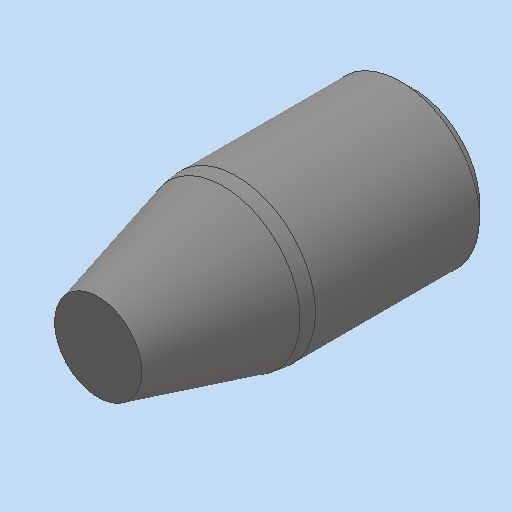
# Autodesk Inventor part: MM0948AN100_G01_125
Saved by Autodesk Inventor 2023.3 (Build 273359000, 359)
## iProperties
Created: 2023-03-23
Part Number: MM0948AN100_G01_125
Material: 1.2379 X155CrVMo12-1
Description: =<RBPARTNOTITLE2>
Document SubType Name: Modeling
Designer: ric7an
Mass: 1.92974 g
Surface Area: 2.93738 cm^2
Volume: 0.245827 cm^3
Density: 7.85 g/cm^3
Appearance: Stahl - rostfrei AnP
AnP_Kategorie: 1
AnP_Material: =<Material>
MaxAbmaße: 6 x 12 x 6 (FM)
AnP_TemplVers: 20200821
RBDOCUMENTTYPE: DRF
RBDOCUMENTVERSION: 00
RBDRAWINGMAINSCALE: 1:1
RBDRAWINGMISSINGSPEC: --
RBDRAWINGVOLUME: --
RBDSV1: 0850
RBGBEDGESIN1: +0,5
RBGBEDGESIN2: +0,2
RBGBEDGESOUT1: -0,3
RBGBEDGESOUT2: -0,1
RBMATERIAL: =<Material>
RBMATMEETS: --
RBMATNO: =<Part Number>
RBPARTMADEOF: Ø6 x 12 (FM)
RBPARTNO: SIEHE MNR
RBPARTNOTITLE1: manufactured part
RBPARTNOTITLE2: Anfertigungsteil
RBPARTSAFETYINDICATOR: --
RBSURFACE: --
RBSURFACE2: --
RBZEDGESNORM: ISO13715:2002-06
RBZGENDIMCLASS: m
RBZGENDIMNORM: ISO 2768-1:1989-11
RBZGENGEOCLASS: H
RBZGENGEONORM: ISO 2768-2:1989-11
RBZSURFACENORM: ISO13D2:2002-02
RBZTOLERANCENORM: ISO 14405-1:2010-12
AnP_Kommentar_aktuell: =<Comments>
AnP_Material_aktuell: =<Material>
Author: FH/Wi
Keywords: =<RBPARTMADEOF>
Comments: =<RBSURFACE2>
Revision Number: 01
Autodesk Inventor part; units mm, degrees
ref_plane "YZ Plane" through (0, 0, 0) normal (1, 0, 0) x (0, 1, 0)
ref_plane "XZ Plane" through (0, 0, 0) normal (0, 1, 0) x (-1, 0, 0)
ref_plane "XY Plane" through (0, 0, 0) normal (0, 0, 1) x (1, 0, 0)
sketch "Skizze1" plane through (0, 0, 0) normal (0, 0, 1) x (1, 0, 0)
  line L0 (0, 14.4) -> (0, -2.4) projected
  line L1 (-3.6, 0) -> (0.6, 0) projected
  line L2 (-1.6603, 0) -> (-3, 5)
  line L3 (-3, 5) -> (-3, 12)
  line L4 (-3, 12) -> (0, 12)
  point P0 (0, 0)
  dimension "d0" = 3
  dimension "d1" = 15
  dimension "d2" = 5
  dimension "d3" = 7
  constraints: 6 end point, 2 point on line, 1 perpendicular, 1 vertical
  measures "d0" distance of L3.end L4.end
  measures "d1" angle of L3 L2
  measures "d2" vertical distance of L2.start L2.end
  measures "d3" distance of L2.end L3.end
revolve "Umdrehung1" add sketch "Skizze1" angle 360 about axis through (0, 0, 0) along (0, -1, 0)
sketch "Skizze2" plane through (0, 12, 0) normal (0, 1, 0) x (1, 0, 0)
  circle A0 centre (0, 0) radius 3 projected
  line L0 (-1.6583, 3) -> (1.6583, 3)
  line L1 (1.6583, 3) -> (1.6583, 2.5)
  line L2 (1.6583, 2.5) -> (-1.6583, 2.5)
  line L3 (-1.6583, 2.5) -> (-1.6583, 3)
  dimension "d5" = 0.5
  constraints: 8 end point, 2 parallel, 2 point on circle, 1 horizontal, 1 perpendicular, 1 tangent
  measures "d5" distance of L0.end L1.end
extrude "Extrusion1" cut sketch "Skizze2" against normal blind 3 contours L2 A0 picked at (0, 2.6667)
sketch "Skizze3" plane through (0, 12, 0) normal (0, 1, 0) x (1, 0, 0)
  point P0 (0, 0)
  point P1 (0, 0)
  constraints: 1 coincident
hole "Bohrung1" at (0, 12, 0) direction (0, -1, 0) diameter 2.459 depth 7 tip angle 118 thread size "M3x0.5" designation "M3" class "6H" standard "ISO Metric profile"
chamfer "Fase1" distance 0.5 angle 45 2 edges at (1.4186, 12, 2.6434) (-2.6434, 12, -1.4186)
fillet "Rundung1" radius 2 1 edges at (3, 5, 0)
